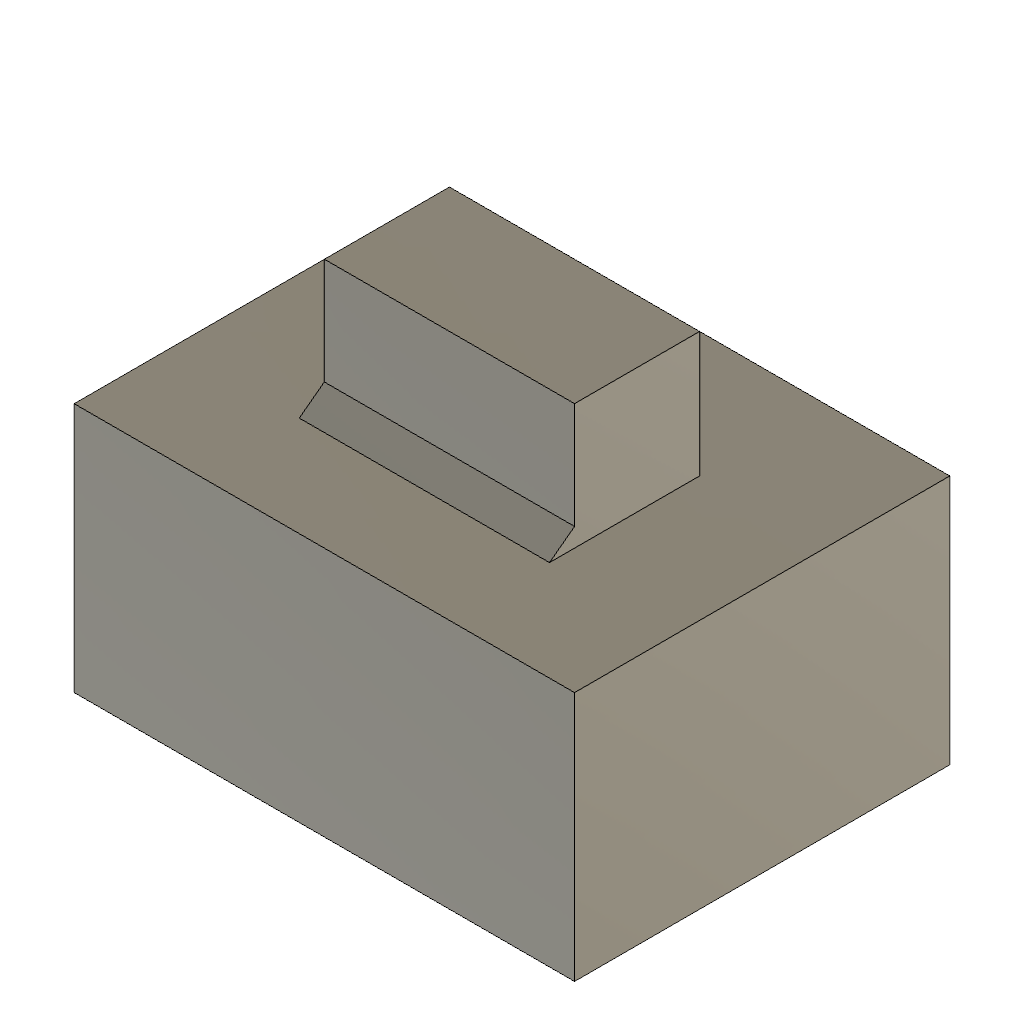
vendor_BevelPostTwo (Autodesk Fusion 360 design; units mm, degrees)
Autodesk Fusion 360 part; units mm, degrees
sketch "Base sketch" plane through (0, 0, 0) normal (0, 0, 1) x (1, 0, 0)
  line L0 (0, 0) -> (40, 0)
  line L1 (40, 0) -> (40, 30)
  line L2 (40, 30) -> (0, 30)
  line L3 (0, 30) -> (0, 0)
extrude "Base extrude" add sketch "Base sketch" along normal blind 20
sketch "Post sketch" plane through (0, 0, 0) normal (0, 0, 1) x (1, 0, 0)
  line L0 (10, 10) -> (30, 10)
  line L1 (30, 10) -> (30, 20)
  line L2 (30, 20) -> (10, 20)
  line L3 (10, 20) -> (10, 10)
extrude "Post extrude" add sketch "Post sketch" along normal blind 30
chamfer "Post bevel" distance 2 distance2 1.5 1 edges at (20, 10, 20) measured on face at (16.6667, 3.3333, 20) tangent chain off
equation "height = 20.0 mm"
